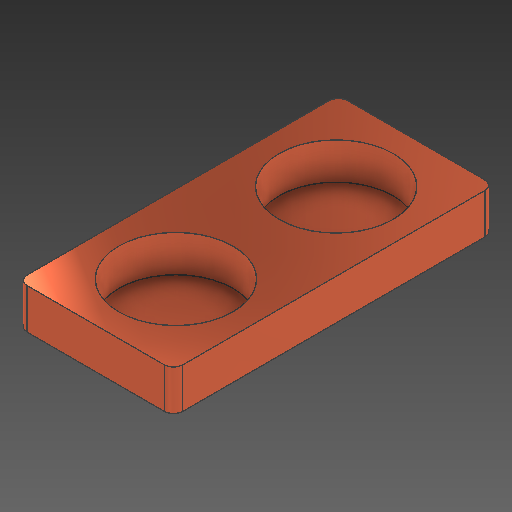
# Autodesk Inventor part: Base para cojinetesipt
Saved by Autodesk Inventor 2026.1 (Build 301233020, 233B)
## iProperties
Created: 2026-10-19
Part Number: Base para cojinetesipt
Material: Generic
Document SubType Name: Modeling
Designer: YmCris
Density: 1 g/cm^3
Appearance: Default
Author: YmCris
Autodesk Inventor part; units mm, degrees
ref_plane "YZ Plane" through (0, 0, 0) normal (1, 0, 0) x (0, 1, 0)
ref_plane "XZ Plane" through (0, 0, 0) normal (0, 1, 0) x (-1, 0, 0)
ref_plane "XY Plane" through (0, 0, 0) normal (0, 0, 1) x (1, 0, 0)
sketch "Sketch1" plane through (0, 0, 0) normal (0, 1, 0) x (-1, 0, 0)
  line L0 (37.5, 87.5) -> (-37.5, 87.5)
  line L1 (-42.5, 82.5) -> (-42.5, -82.5)
  line L2 (-37.5, -87.5) -> (37.5, -87.5)
  line L3 (42.5, -82.5) -> (42.5, 82.5)
  arc A0 (42.5, 85.5) -> (40.5, 87.5) centre (40.5, 85.5) ccw
  arc A1 (-37.5, 87.5) -> (-42.5, 82.5) centre (-37.5, 82.5) ccw
  arc A2 (37.5, -87.5) -> (42.5, -82.5) centre (37.5, -82.5) ccw
  arc A3 (42.5, 82.5) -> (37.5, 87.5) centre (37.5, 82.5) ccw
  arc A4 (-42.5, -82.5) -> (-37.5, -87.5) centre (-37.5, -82.5) ccw
  point P0 (-42.5, -87.5)
  point P1 (-42.5, 87.5)
  point P2 (42.5, -87.5)
  dimension "d0" = 85
  dimension "d1" = 175
  dimension "d2" = 2
  dimension "d3" = 5
  dimension "d4" = 5
  constraints: 10 point on circle, 10 tangent, 8 end point, 8 point on line, 5 centre point, 2 equal radius, 2 parallel, 1 horizontal, 1 perpendicular
  measures "d0" distance of point (42.5, -87.5) point (-42.5, -87.5)
  measures "d1" distance of point (-42.5, -87.5) point (-42.5, 87.5)
  measures "d2" radius of A0
  measures "d3" radius of A1
  measures "d4" radius of A4
extrude "Extrusion1" add sketch "Sketch1" along normal blind 22
sketch "Sketch2" plane through (0, 22, 0) normal (0, 1, 0) x (1, 0, 0)
  circle A0 centre (0, 43.75) radius 31.15
  line L0 (-31.15, 0) -> (31.15, 0) construction
  circle A1 centre (0, -43.75) radius 31.15
  point P0 (0, 0)
  dimension "d7" = 62.3
  constraints: 2 centre point, 2 end point, 1 horizontal, 1 symmetric about line, 1 other
  measures "d7" diameter of A0
extrude "Extrusion2" cut sketch "Sketch2" against normal blind 20 contours A0
sketch "Sketch3" plane through (0, 22, 0) normal (0, 1, 0) x (1, 0, 0)
  circle A0 centre (0, -43.75) radius 31.15
  point P0 (0, 0)
  dimension "d10" = 62.3
  constraints: 1 centre point
  measures "d10" diameter of A0
extrude "Extrusion3" cut sketch "Sketch3" against normal blind 20
body "Solid1"
